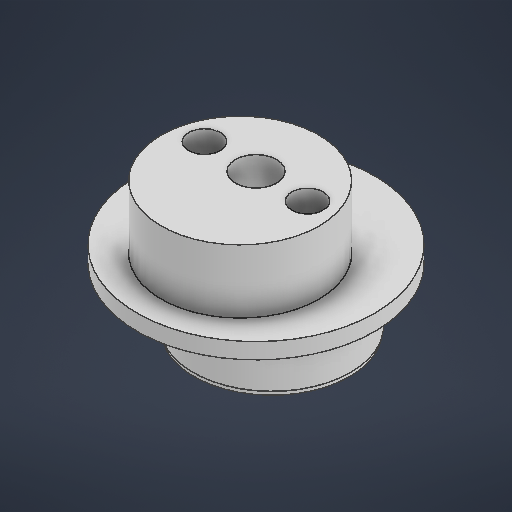
# Autodesk Inventor part: s2_v2
Saved by Autodesk Inventor 2026.2 (Build 302298010, 298A)
## iProperties
Created: 2026-04-01
Part Number: s2_v2
Material: 일반
Document SubType Name: Modeling
Designer: work
Density: 1 g/cm^3
Appearance: 기본값
Author: work
Autodesk Inventor part; units mm, degrees
ref_plane "YZ Plane" through (0, 0, 0) normal (1, 0, 0) x (0, 1, 0)
ref_plane "XZ Plane" through (0, 0, 0) normal (0, 1, 0) x (-1, 0, 0)
sketch "스케치1" plane through (0, 0, 0) normal (0, 1, 0) x (-1, 0, 0)
  circle A0 centre (0, 0) radius 10
  dimension "d0" = 20
  constraints: 1 centre point, 1 coincident
  measures "d0" diameter of A0
extrude "돌출1" add sketch "스케치1" along normal blind 5
sketch "스케치2" plane through (0, 5, 0) normal (0, 1, 0) x (1, 0, 0)
  circle A0 centre (0, 0) radius 15
  dimension "d3" = 30
  constraints: 1 centre point, 1 coincident
  measures "d3" diameter of A0
extrude "돌출2" add sketch "스케치2" along normal blind 2
sketch "스케치3" plane through (0, 7, 0) normal (0, 1, 0) x (1, 0, 0)
  line L0 (0, 0) -> (0, 2) construction
  circle A0 centre (0, 2) radius 9.95
  dimension "d6" = 2
  dimension "d7" = 19.9
  constraints: 2 end point, 1 centre point, 1 coincident, 1 vertical
  measures "d6" distance of L0.start L0.end
  measures "d7" diameter of A0
extrude "돌출3" add sketch "스케치3" along normal blind 8
sketch "스케치4" plane through (0, 15, -2) normal (0, 1, 0) x (1, 0, 0)
  circle A0 centre (0, -2) radius 10 projected
  circle A1 centre (0, -2) radius 15
  dimension "d10" = 30
  constraints: 1 centre point, 1 coincident
  measures "d10" diameter of A1
extrude "돌출4" add sketch "스케치4" along normal blind 2 contours A0 | A1
sketch "스케치5" plane through (0, 17, 0) normal (0, 1, 0) x (1, 0, 0)
  line L0 (0, 0) -> (0, -2) construction
  circle A0 centre (0, -2) radius 9.95
  dimension "d13" = 2
  dimension "d14" = 19.9
  constraints: 2 end point, 1 centre point, 1 coincident, 1 vertical
  measures "d13" distance of L0.start L0.end
  measures "d14" diameter of A0
extrude "돌출5" add sketch "스케치5" along normal blind 8
sketch "스케치6" plane through (0, 25, 2) normal (0, 1, 0) x (1, 0, 0)
  circle A0 centre (0, 2) radius 2.6
  line L0 (6.5, 2) -> (-6.5, 2) construction
  line L1 (0, 2) -> (0, -0.6) construction
  circle A1 centre (-6.5, 2) radius 2
  circle A2 centre (6.5, 2) radius 2
  dimension "d17" = 5.2
  dimension "d18" = 13
  dimension "d19" = 4
  dimension "d20" = 4
  constraints: 4 end point, 3 coincident, 2 centre point, 1 horizontal, 1 midpoint, 1 vertical, 1 vertical alignment, 2 other
  measures "d18" distance of L0.start L0.end
  measures "d19" diameter of A1
  measures "d20" diameter of A2
extrude "돌출6" cut sketch "스케치6" against normal through all
sketch "스케치7" plane through (0, 0, 0) normal (0, -1, 0) x (1, 0, 0)
  circle A0 centre (-6.5, 0) radius 2 projected
  circle A1 centre (6.5, 0) radius 2 projected
  circle A2 centre (0, 0) radius 2.6 projected
  circle A3 centre (0, 0) radius 10 projected
  circle A4 centre (6.5, 0) radius 3.05
  circle A5 centre (-6.5, 0) radius 3.05
  dimension "d23" = 6.1
  dimension "d24" = 6.1
  constraints: 2 centre point, 2 coincident
  measures "d23" diameter of A4
  measures "d24" diameter of A5
extrude "돌출7" cut sketch "스케치7" against normal blind 3 contours A0 | A1 | A4 | A5
sketch "스케치8" plane through (0, 0, 0) normal (0, 0, 1) x (1, 0, 0)
  circle A0 centre (0, 2.5) radius 1.5
  line L0 (0, 2.5) -> (0, 0) construction
  dimension "d27" = 3
  dimension "d28" = 2.5
  constraints: 2 end point, 1 centre point, 1 vertical
  measures "d27" diameter of A0
  measures "d28" distance of L0.end L0.start
extrude "돌출8" cut sketch "스케치8" against normal through all
ref_plane "작업 평면1" through (0, 7, 0) normal (0, 1, 0) x (1, 0, 0)
split_face "분할1"
sketch "스케치9" plane through (0, 0, 0) normal (1, 0, 0) x (0, 1, 0)
  line L0 (5, 15) -> (7, 15) projected
  line L1 (7, 15) -> (-14.0798, 15)
  line L2 (-14.0798, 15) -> (-14.0798, -19.3989)
  line L3 (-14.0798, -19.3989) -> (7, -19.3989)
  line L4 (7, -19.3989) -> (7, 15)
  point P0 (0, 0)
  constraints: 8 end point, 2 parallel, 1 horizontal, 1 perpendicular, 1 point on line
extrude "돌출9" cut sketch "스케치9" along normal through all both and the other way through all
sketch "스케치10" plane through (0, 7, -2) normal (0, -1, 0) x (1, 0, 0)
  circle A0 centre (-6.5, 2) radius 2 projected
  circle A1 centre (6.5, 2) radius 2 projected
  circle A2 centre (0, 2) radius 2.6 projected
  circle A3 centre (0, 0) radius 9.95 projected
  circle A4 centre (0, 0) radius 9.85
  dimension "d34" = 19.7
  constraints: 1 centre point, 1 coincident
  measures "d34" diameter of A4
extrude "돌출10" add sketch "스케치10" along normal blind 0.5 contours A4
chamfer "모따기1" distance 0.1 angle 45 1 edges at (-9.85, 7, -2)
